Autodesk Fusion 360 part; units mm, degrees
(part 2 of 3)
  spline S18 degree 5 poles (-4.9086, 5.0572) (-4.9127, 5.0613) (-4.9209, 5.0695) (-4.9336, 5.0813) (-4.9513, 5.0962) (-4.9744, 5.1137) (-4.9983, 5.1304) (-5.0226, 5.1466) (-5.0473, 5.1625) (-5.0721, 5.1783) (-5.097, 5.1938) (-5.1223, 5.2091) (-5.1478, 5.224) (-5.1737, 5.2385) (-5.2, 5.2525) (-5.2266, 5.2662) (-5.2535, 5.2796) (-5.2806, 5.2926) (-5.3079, 5.3054) (-5.3354, 5.318) (-5.3631, 5.3303) (-5.391, 5.3423) (-5.4191, 5.3541) (-5.4474, 5.3656) (-5.476, 5.3768) (-5.5047, 5.3878) (-5.5336, 5.3984) (-5.5627, 5.4089) (-5.592, 5.4191) (-5.6215, 5.429) (-5.6511, 5.4387) (-5.6809, 5.4482) (-5.7108, 5.4574) (-5.7409, 5.4664) (-5.7712, 5.4751) (-5.8016, 5.4836) (-5.8322, 5.4919) (-5.8629, 5.4999) (-5.8938, 5.5077) (-5.9248, 5.5153) (-5.9559, 5.5226) (-5.9872, 5.5297) (-6.0186, 5.5366) (-6.0501, 5.5433) (-6.0818, 5.5497) (-6.1136, 5.5559) (-6.1456, 5.5619) (-6.1776, 5.5676) (-6.2098, 5.5731) (-6.2421, 5.5784) (-6.2745, 5.5835) (-6.307, 5.5884) (-6.3397, 5.593) (-6.3724, 5.5975) (-6.4053, 5.6017) (-6.4383, 5.6056) (-6.4713, 5.6094) (-6.5045, 5.613) (-6.5378, 5.6163) (-6.5712, 5.6194) (-6.6046, 5.6223) (-6.6382, 5.625) (-6.6719, 5.6274) (-6.7056, 5.6297) (-6.7395, 5.6317) (-6.7734, 5.6335) (-6.8075, 5.6351) (-6.8416, 5.6365) (-6.8758, 5.6377) (-6.9101, 5.6386) (-6.9444, 5.6394) (-6.972, 5.6398) (-6.9927, 5.64) (-7.0065, 5.6401) (-7.0134, 5.6402) knots 0 0 0 0 0 0 0.01428571 0.02857143 0.04285714 0.05714286 0.07142857 0.08571429 0.1 0.11428571 0.12857143 0.14285714 0.15714286 0.17142857 0.18571429 0.2 0.21428571 0.22857143 0.24285714 0.25714286 0.27142857 0.28571429 0.3 0.31428571 0.32857143 0.34285714 0.35714286 0.37142857 0.38571429 0.4 0.41428571 0.42857143 0.44285714 0.45714286 0.47142857 0.48571429 0.5 0.51428571 0.52857143 0.54285714 0.55714286 0.57142857 0.58571429 0.6 0.61428571 0.62857143 0.64285714 0.65714286 0.67142857 0.68571429 0.7 0.71428571 0.72857143 0.74285714 0.75714286 0.77142857 0.78571429 0.8 0.81428571 0.82857143 0.84285714 0.85714286 0.87142857 0.88571429 0.9 0.91428571 0.92857143 0.94285714 0.95714286 0.97142857 0.98571429 1 1 1 1 1 1
  arc A38 (-7.0134, 5.6402) -> (-7.5314, 4.9273) centre (0, 0) ccw
  spline S19 degree 5 poles (-7.5314, 4.9273) (-7.5292, 4.9207) (-7.5249, 4.9076) (-7.5182, 4.888) (-7.5093, 4.8619) (-7.498, 4.8294) (-7.4865, 4.7971) (-7.4748, 4.765) (-7.4629, 4.7329) (-7.4509, 4.7011) (-7.4387, 4.6693) (-7.4263, 4.6378) (-7.4137, 4.6064) (-7.401, 4.5751) (-7.3881, 4.544) (-7.375, 4.5131) (-7.3617, 4.4823) (-7.3482, 4.4516) (-7.3346, 4.4212) (-7.3208, 4.3909) (-7.3068, 4.3608) (-7.2927, 4.3308) (-7.2784, 4.301) (-7.2639, 4.2714) (-7.2492, 4.242) (-7.2343, 4.2127) (-7.2193, 4.1837) (-7.2041, 4.1548) (-7.1887, 4.1261) (-7.1732, 4.0976) (-7.1574, 4.0692) (-7.1415, 4.0411) (-7.1255, 4.0131) (-7.1092, 3.9854) (-7.0928, 3.9578) (-7.0762, 3.9305) (-7.0594, 3.9033) (-7.0425, 3.8764) (-7.0253, 3.8496) (-7.008, 3.8231) (-6.9905, 3.7968) (-6.9729, 3.7707) (-6.955, 3.7449) (-6.937, 3.7192) (-6.9188, 3.6938) (-6.9004, 3.6687) (-6.8819, 3.6437) (-6.8631, 3.619) (-6.8442, 3.5946) (-6.8251, 3.5704) (-6.8058, 3.5464) (-6.7863, 3.5227) (-6.7667, 3.4993) (-6.7468, 3.4763) (-6.7267, 3.4534) (-6.7064, 3.4309) (-6.686, 3.4086) (-6.6654, 3.3866) (-6.6446, 3.3649) (-6.6236, 3.3434) (-6.6024, 3.3224) (-6.5809, 3.3017) (-6.5591, 3.2816) (-6.537, 3.2619) (-6.5147, 3.2426) (-6.4922, 3.2236) (-6.4695, 3.2049) (-6.4468, 3.1864) (-6.4239, 3.1683) (-6.4006, 3.1507) (-6.3768, 3.1341) (-6.3572, 3.1219) (-6.342, 3.1135) (-6.3317, 3.1082) (-6.3265, 3.1056) knots -1 -1 -1 -1 -1 -1 -0.98571429 -0.97142857 -0.95714286 -0.94285714 -0.92857143 -0.91428571 -0.9 -0.88571429 -0.87142857 -0.85714286 -0.84285714 -0.82857143 -0.81428571 -0.8 -0.78571429 -0.77142857 -0.75714286 -0.74285714 -0.72857143 -0.71428571 -0.7 -0.68571429 -0.67142857 -0.65714286 -0.64285714 -0.62857143 -0.61428571 -0.6 -0.58571429 -0.57142857 -0.55714286 -0.54285714 -0.52857143 -0.51428571 -0.5 -0.48571429 -0.47142857 -0.45714286 -0.44285714 -0.42857143 -0.41428571 -0.4 -0.38571429 -0.37142857 -0.35714286 -0.34285714 -0.32857143 -0.31428571 -0.3 -0.28571429 -0.27142857 -0.25714286 -0.24285714 -0.22857143 -0.21428571 -0.2 -0.18571429 -0.17142857 -0.15714286 -0.14285714 -0.12857143 -0.11428571 -0.1 -0.08571429 -0.07142857 -0.05714286 -0.04285714 -0.02857143 -0.01428571 0 0 0 0 0 0
  line L19 (-6.3265, 3.1056) -> (-5.2636, 2.5839)
  arc A39 (-5.2172, 2.4516) -> (-5.2636, 2.5839) centre (-5.3077, 2.4941) ccw
  circle A40 centre (0, 0) radius 2.35
  dimension "d41" = 0.1
sketch "Diametrial Pitch Circle" plane through (0, 0, 0) normal (0, 0, 1) x (1, 0, 0)
  circle A0 centre (0, 0) radius 7.5 construction
sketch "Sketch6" plane through (0, 0, 0) normal (1, 0, 0) x (0, 1, 0)
  line L0 (0, 0) -> (0, 5)
  line L1 (0, 5) -> (10, 5)
  line L2 (10, 5) -> (10, 0)
  line L3 (10, 0) -> (0, 0)
  dimension "d13" = 5
  dimension "d14" = 10
  constraint coincident L0.start L3.end
  constraint vertical L0
  constraint perpendicular L0 L1
  constraint perpendicular L1 L2
  constraint perpendicular L0 L3
  measures "d13" distance of L0.start L0.end
  measures "d14" distance of L0.end L1.end
extrude "Extrude4" add sketch "Sketch6" along normal blind 38 separate body makes body 2
sketch "Sketch7" plane through (0, 10, 0) normal (0, 1, 0) x (-1, 0, 0)
  line L0 (0, 0) -> (0, 5)
  line L1 (0, 5) -> (-38, 5)
  line L2 (-38, 5) -> (-38, 0)
  line L3 (-38, 0) -> (0, 0)
  line L4 (-38, 5) -> (-30, 5)
  line L5 (-30, 5) -> (-30, 0)
  line L6 (-30, 0) -> (-38, 0)
  line L7 (-38, 0) -> (-38, 5)
  constraint horizontal L4
  constraint vertical L5
  constraint horizontal L6
  constraint vertical L7
  constraint coincident L3 L5.end
  constraint coincident L1.end L2.start
extrude "Extrude5" add sketch "Sketch7" along normal blind 110 contours L1 L2 L3 L4 L5 L6 L7 bodies 2
sketch "Sketch8" plane through (30, 0, 0) normal (-1, 0, 0) x (0, -1, 0)
  line L0 (-10, 0) -> (-10, 5)
  line L1 (-10, 5) -> (-120, 5)
  line L2 (-120, 5) -> (-120, 0)
  line L3 (-120, 0) -> (-10, 0)
  line L4 (-120, 5) -> (-110, 5)
  line L5 (-110, 5) -> (-110, 0)
  line L6 (-110, 0) -> (-120, 0)
  line L7 (-120, 0) -> (-120, 5)
  dimension "d19" = 10
  dimension "d20" = 5
  constraint horizontal L4
  constraint vertical L5
  constraint horizontal L6
  constraint vertical L7
  constraint coincident L1.end L2.start
  measures "d19" distance of L1.end L4.end
  measures "d20" distance of L1.end L2.end
extrude "Extrude6" add sketch "Sketch8" along normal blind 25 contours L1 L2 L3 L4 L5 L6 L7 bodies 2
sketch "Sketch9" plane through (0, 0, 5) normal (0, 0, 1) x (-1, 0, 0)
  line L0 (0, -10) -> (0, 0)
  line L1 (0, 0) -> (-38, 0)
  line L2 (-38, 0) -> (-38, -120)
  line L3 (-38, -120) -> (-5, -120)
  line L4 (-5, -120) -> (-5, -110)
  line L5 (-5, -110) -> (-30, -110)
  line L6 (-30, -110) -> (-30, -10)
  line L7 (-30, -10) -> (0, -10)
  line L8 (-38, -5) -> (-25, 0)
  line L9 (-38, -110) -> (-30, -120)
  line L10 (-30, -110) -> (-5, -120)
  line L11 (0, -4.5) -> (0, 0)
  line L12 (-4.5, 0) -> (0, 0)
  arc A0 (-4.5, 0) -> (0, -4.5) centre (0, 0) ccw
  circle A1 centre (0, 0) radius 2.35
  circle A2 centre (0, 0) radius 8.5
  dimension "d25" = 9
  dimension "d28" = 4.7
  dimension "d31" = 17
  constraint coincident L2 L8.start
  constraint coincident L1 L8.end
  constraint coincident L2 L9.start
  constraint coincident L3 L9.end
  constraint coincident L5.end L6.start
  constraint coincident L3.end L4.start
  constraint coincident L0.end L1.start
  constraint coincident L0 L11.start
  constraint coincident L1 L12.start
  constraint concentric A0 A2
  measures "d25" diameter of A0
  measures "d28" diameter of A1
  measures "d31" diameter of A2
extrude "Extrude7" cut sketch "Sketch9" against normal blind 20 contours L4 L5 L10 | L1 L2 L8 | L2 L3 L9 bodies 2
extrude "Extrude8" cut sketch "Sketch9" against normal blind 2 contours L0 L1 L11 L12 A0 A1 | L0 L1 L11 L12 A1 picked at (-1.5587, -0.1115) bodies 2
extrude "Extrude9" cut sketch "Sketch9" against normal blind 20 contours L0 L1 L11 L12 A1 picked at (-1.5587, -0.1115) bodies 2
split "Split3" by plane through (0, 0, 2) normal (0, 0, 1) bodies 1 2 makes body 3 at (21.6667, 116.6667, 5)
combine "Combine1" operation add target body 3 tool bodies 2
copy_body "CopyPasteBodies2" bodies 1 makes body 4
move_body "Move3" bodies 4 to x (1, 0, 0) y (0, 1, 0) z (0, 0, 1) at (-15, 0, 0)
move_body "Move4" bodies 1 to x (0.951057, 0.309017, 0) y (-0.309017, 0.951057, 0) z (0, 0, 1) at (0, 0, 0)
mirror "Mirror2" about plane through (0, 0, 0) normal (1, 0, 0) of bodies 3 makes body 5
move_body "Move5" bodies 5 to x (1, 0, 0) y (0, 1, 0) z (0, 0, 1) at (-15, 0, 0)
move_body "Move6" bodies 3 1 to x (1, 0, 0) y (0, 1, 0) z (0, 0, 1) at (15, 0, 0)
sketch "Sketch15" plane through (0, 0, 2) normal (0, 0, 1) x (-1, 0, 0)
  arc A0 (9.7828, 2.4516) -> (9.3382, 1.0832) centre (15, 0) ccw
  arc A1 (9.2229, 1.0035) -> (9.3382, 1.0832) centre (9.24, 1.102) ccw
  line L0 (9.2229, 1.0035) -> (8.0563, 1.2061)
  spline S0 degree 5 poles (8.0563, 1.2061) (8.0506, 1.2071) (8.0391, 1.2089) (8.0219, 1.211) (7.9989, 1.2127) (7.9699, 1.2132) (7.9407, 1.2127) (7.9115, 1.2115) (7.8822, 1.2099) (7.8529, 1.208) (7.8236, 1.2059) (7.7942, 1.2034) (7.7647, 1.2005) (7.7353, 1.197) (7.7057, 1.1929) (7.6762, 1.1884) (7.6466, 1.1833) (7.617, 1.178) (7.5874, 1.1723) (7.5578, 1.1663) (7.5281, 1.1599) (7.4985, 1.1533) (7.4688, 1.1463) (7.4391, 1.139) (7.4094, 1.1313) (7.3798, 1.1232) (7.3501, 1.1148) (7.3204, 1.1062) (7.2907, 1.0972) (7.2611, 1.0879) (7.2314, 1.0784) (7.2017, 1.0685) (7.1721, 1.0584) (7.1425, 1.048) (7.1128, 1.0372) (7.0832, 1.0262) (7.0536, 1.015) (7.0241, 1.0034) (6.9945, 0.9916) (6.965, 0.9795) (6.9355, 0.9671) (6.906, 0.9545) (6.8765, 0.9416) (6.8471, 0.9284) (6.8177, 0.915) (6.7883, 0.9013) (6.759, 0.8874) (6.7296, 0.8732) (6.7004, 0.8587) (6.6711, 0.844) (6.6419, 0.8291) (6.6127, 0.8139) (6.5836, 0.7985) (6.5545, 0.7828) (6.5254, 0.7669) (6.4964, 0.7508) (6.4675, 0.7344) (6.4385, 0.7177) (6.4097, 0.7009) (6.3808, 0.6838) (6.352, 0.6664) (6.3233, 0.6489) (6.2946, 0.6311) (6.266, 0.613) (6.2374, 0.5948) (6.2089, 0.5763) (6.1804, 0.5576) (6.152, 0.5387) (6.1236, 0.5195) (6.0953, 0.5001) (6.0671, 0.4805) (6.0445, 0.4647) (6.0277, 0.4527) (6.0164, 0.4446) (6.0108, 0.4406) knots 0 0 0 0 0 0 0.01428571 0.02857143 0.04285714 0.05714286 0.07142857 0.08571429 0.1 0.11428571 0.12857143 0.14285714 0.15714286 0.17142857 0.18571429 0.2 0.21428571 0.22857143 0.24285714 0.25714286 0.27142857 0.28571429 0.3 0.31428571 0.32857143 0.34285714 0.35714286 0.37142857 0.38571429 0.4 0.41428571 0.42857143 0.44285714 0.45714286 0.47142857 0.48571429 0.5 0.51428571 0.52857143 0.54285714 0.55714286 0.57142857 0.58571429 0.6 0.61428571 0.62857143 0.64285714 0.65714286 0.67142857 0.68571429 0.7 0.71428571 0.72857143 0.74285714 0.75714286 0.77142857 0.78571429 0.8 0.81428571 0.82857143 0.84285714 0.85714286 0.87142857 0.88571429 0.9 0.91428571 0.92857143 0.94285714 0.95714286 0.97142857 0.98571429 1 1 1 1 1 1
  arc A2 (6.0108, 0.4406) -> (6.0108, -0.4406) centre (15, 0) ccw
  spline S1 degree 5 poles (6.0108, -0.4406) (6.0164, -0.4446) (6.0277, -0.4527) (6.0445, -0.4647) (6.0671, -0.4805) (6.0953, -0.5001) (6.1236, -0.5195) (6.152, -0.5387) (6.1804, -0.5576) (6.2089, -0.5763) (6.2374, -0.5948) (6.266, -0.613) (6.2946, -0.6311) (6.3233, -0.6489) (6.352, -0.6664) (6.3808, -0.6838) (6.4097, -0.7009) (6.4385, -0.7177) (6.4675, -0.7344) (6.4964, -0.7508) (6.5254, -0.7669) (6.5545, -0.7828) (6.5836, -0.7985) (6.6127, -0.8139) (6.6419, -0.8291) (6.6711, -0.844) (6.7004, -0.8587) (6.7296, -0.8732) (6.759, -0.8874) (6.7883, -0.9013) (6.8177, -0.915) (6.8471, -0.9284) (6.8765, -0.9416) (6.906, -0.9545) (6.9355, -0.9671) (6.965, -0.9795) (6.9945, -0.9916) (7.0241, -1.0034) (7.0536, -1.015) (7.0832, -1.0262) (7.1128, -1.0372) (7.1425, -1.048) (7.1721, -1.0584) (7.2017, -1.0685) (7.2314, -1.0784) (7.2611, -1.0879) (7.2907, -1.0972) (7.3204, -1.1062) (7.3501, -1.1148) (7.3798, -1.1232) (7.4094, -1.1313) (7.4391, -1.139) (7.4688, -1.1463) (7.4985, -1.1533) (7.5281, -1.1599) (7.5578, -1.1663) (7.5874, -1.1723) (7.617, -1.178) (7.6466, -1.1833) (7.6762, -1.1884) (7.7057, -1.1929) (7.7353, -1.197) (7.7647, -1.2005) (7.7942, -1.2034) (7.8236, -1.2059) (7.8529, -1.208) (7.8822, -1.2099) (7.9115, -1.2115) (7.9407, -1.2127) (7.9699, -1.2132) (7.9989, -1.2127) (8.0219, -1.211) (8.0391, -1.2089) (8.0506, -1.2071) (8.0563, -1.2061) knots -1 -1 -1 -1 -1 -1 -0.98571429 -0.97142857 -0.95714286 -0.94285714 -0.92857143 -0.91428571 -0.9 -0.88571429 -0.87142857 -0.85714286 -0.84285714 -0.82857143 -0.81428571 -0.8 -0.78571429 -0.77142857 -0.75714286 -0.74285714 -0.72857143 -0.71428571 -0.7 -0.68571429 -0.67142857 -0.65714286 -0.64285714 -0.62857143 -0.61428571 -0.6 -0.58571429 -0.57142857 -0.55714286 -0.54285714 -0.52857143 -0.51428571 -0.5 -0.48571429 -0.47142857 -0.45714286 -0.44285714 -0.42857143 -0.41428571 -0.4 -0.38571429 -0.37142857 -0.35714286 -0.34285714 -0.32857143 -0.31428571 -0.3 -0.28571429 -0.27142857 -0.25714286 -0.24285714 -0.22857143 -0.21428571 -0.2 -0.18571429 -0.17142857 -0.15714286 -0.14285714 -0.12857143 -0.11428571 -0.1 -0.08571429 -0.07142857 -0.05714286 -0.04285714 -0.02857143 -0.01428571 0 0 0 0 0 0
  line L1 (8.0563, -1.2061) -> (9.2229, -1.0035)
  arc A3 (9.3382, -1.0832) -> (9.2229, -1.0035) centre (9.24, -1.102) ccw
  arc A4 (9.3382, -1.0832) -> (9.7828, -2.4516) centre (15, 0) ccw
  arc A5 (9.7364, -2.5839) -> (9.7828, -2.4516) centre (9.6923, -2.4941) ccw
  line L2 (9.7364, -2.5839) -> (8.6735, -3.1056)
  spline S2 degree 5 poles (8.6735, -3.1056) (8.6683, -3.1082) (8.658, -3.1135) (8.6428, -3.1219) (8.6232, -3.1341) (8.5994, -3.1507) (8.5761, -3.1683) (8.5532, -3.1864) (8.5305, -3.2049) (8.5078, -3.2236) (8.4853, -3.2426) (8.463, -3.2619) (8.4409, -3.2816) (8.4191, -3.3017) (8.3976, -3.3224) (8.3764, -3.3434) (8.3554, -3.3649) (8.3346, -3.3866) (8.314, -3.4086) (8.2936, -3.4309) (8.2733, -3.4534) (8.2532, -3.4763) (8.2333, -3.4993) (8.2137, -3.5227) (8.1942, -3.5464) (8.1749, -3.5704) (8.1558, -3.5946) (8.1369, -3.619) (8.1181, -3.6437) (8.0996, -3.6687) (8.0812, -3.6938) (8.063, -3.7192) (8.045, -3.7449) (8.0271, -3.7707) (8.0095, -3.7968) (7.992, -3.8231) (7.9747, -3.8496) (7.9575, -3.8764) (7.9406, -3.9033) (7.9238, -3.9305) (7.9072, -3.9578) (7.8908, -3.9854) (7.8745, -4.0131) (7.8585, -4.0411) (7.8426, -4.0692) (7.8268, -4.0976) (7.8113, -4.1261) (7.7959, -4.1548) (7.7807, -4.1837) (7.7657, -4.2127) (7.7508, -4.242) (7.7361, -4.2714) (7.7216, -4.301) (7.7073, -4.3308) (7.6932, -4.3608) (7.6792, -4.3909) (7.6654, -4.4212) (7.6518, -4.4516) (7.6383, -4.4823) (7.625, -4.5131) (7.6119, -4.544) (7.599, -4.5751) (7.5863, -4.6064) (7.5737, -4.6378) (7.5613, -4.6693) (7.5491, -4.7011) (7.5371, -4.7329) (7.5252, -4.765) (7.5135, -4.7971) (7.502, -4.8294) (7.4907, -4.8619) (7.4818, -4.888) (7.4751, -4.9076) (7.4708, -4.9207) (7.4686, -4.9273) knots 0 0 0 0 0 0 0.01428571 0.02857143 0.04285714 0.05714286 0.07142857 0.08571429 0.1 0.11428571 0.12857143 0.14285714 0.15714286 0.17142857 0.18571429 0.2 0.21428571 0.22857143 0.24285714 0.25714286 0.27142857 0.28571429 0.3 0.31428571 0.32857143 0.34285714 0.35714286 0.37142857 0.38571429 0.4 0.41428571 0.42857143 0.44285714 0.45714286 0.47142857 0.48571429 0.5 0.51428571 0.52857143 0.54285714 0.55714286 0.57142857 0.58571429 0.6 0.61428571 0.62857143 0.64285714 0.65714286 0.67142857 0.68571429 0.7 0.71428571 0.72857143 0.74285714 0.75714286 0.77142857 0.78571429 0.8 0.81428571 0.82857143 0.84285714 0.85714286 0.87142857 0.88571429 0.9 0.91428571 0.92857143 0.94285714 0.95714286 0.97142857 0.98571429 1 1 1 1 1 1
  arc A6 (7.4686, -4.9273) -> (7.9866, -5.6402) centre (15, 0) ccw
  spline S3 degree 5 poles (7.9866, -5.6402) (7.9935, -5.6401) (8.0073, -5.64) (8.028, -5.6398) (8.0556, -5.6394) (8.0899, -5.6386) (8.1242, -5.6377) (8.1584, -5.6365) (8.1925, -5.6351) (8.2266, -5.6335) (8.2605, -5.6317) (8.2944, -5.6297) (8.3281, -5.6274) (8.3618, -5.625) (8.3954, -5.6223) (8.4288, -5.6194) (8.4622, -5.6163) (8.4955, -5.613) (8.5287, -5.6094) (8.5617, -5.6056) (8.5947, -5.6017) (8.6276, -5.5975) (8.6603, -5.593) (8.693, -5.5884) (8.7255, -5.5835) (8.7579, -5.5784) (8.7902, -5.5731) (8.8224, -5.5676) (8.8544, -5.5619) (8.8864, -5.5559) (8.9182, -5.5497) (8.9499, -5.5433) (8.9814, -5.5366) (9.0128, -5.5297) (9.0441, -5.5226) (9.0752, -5.5153) (9.1062, -5.5077) (9.1371, -5.4999) (9.1678, -5.4919) (9.1984, -5.4836) (9.2288, -5.4751) (9.2591, -5.4664) (9.2892, -5.4574) (9.3191, -5.4482) (9.3489, -5.4387) (9.3785, -5.429) (9.408, -5.4191) (9.4373, -5.4089) (9.4664, -5.3984) (9.4953, -5.3878) (9.524, -5.3768) (9.5526, -5.3656) (9.5809, -5.3541) (9.609, -5.3423) (9.6369, -5.3303) (9.6646, -5.318) (9.6921, -5.3054) (9.7194, -5.2926) (9.7465, -5.2796) (9.7734, -5.2662) (9.8, -5.2525) (9.8263, -5.2385) (9.8522, -5.224) (9.8777, -5.2091) (9.903, -5.1938) (9.9279, -5.1783) (9.9527, -5.1625) (9.9774, -5.1466) (10.0017, -5.1304) (10.0256, -5.1137) (10.0487, -5.0962) (10.0664, -5.0813) (10.0791, -5.0695) (10.0873, -5.0613) (10.0914, -5.0572) knots -1 -1 -1 -1 -1 -1 -0.98571429 -0.97142857 -0.95714286 -0.94285714 -0.92857143 -0.91428571 -0.9 -0.88571429 -0.87142857 -0.85714286 -0.84285714 -0.82857143 -0.81428571 -0.8 -0.78571429 -0.77142857 -0.75714286 -0.74285714 -0.72857143 -0.71428571 -0.7 -0.68571429 -0.67142857 -0.65714286 -0.64285714 -0.62857143 -0.61428571 -0.6 -0.58571429 -0.57142857 -0.55714286 -0.54285714 -0.52857143 -0.51428571 -0.5 -0.48571429 -0.47142857 -0.45714286 -0.44285714 -0.42857143 -0.41428571 -0.4 -0.38571429 -0.37142857 -0.35714286 -0.34285714 -0.32857143 -0.31428571 -0.3 -0.28571429 -0.27142857 -0.25714286 -0.24285714 -0.22857143 -0.21428571 -0.2 -0.18571429 -0.17142857 -0.15714286 -0.14285714 -0.12857143 -0.11428571 -0.1 -0.08571429 -0.07142857 -0.05714286 -0.04285714 -0.02857143 -0.01428571 0 0 0 0 0 0
  line L3 (10.0914, -5.0572) -> (10.916, -4.2076)
  arc A7 (11.0562, -4.2043) -> (10.916, -4.2076) centre (10.9878, -4.2772) ccw
  arc A8 (11.0562, -4.2043) -> (12.2202, -5.05) centre (15, 0) ccw
  arc A9 (12.2604, -5.1843) -> (12.2202, -5.05) centre (12.172, -5.1376) ccw
  line L4 (12.2604, -5.1843) -> (11.7072, -6.2312)
  spline S4 degree 5 poles (11.7072, -6.2312) (11.7045, -6.2363) (11.6992, -6.2466) (11.6919, -6.2623) (11.6832, -6.2838) (11.6737, -6.3112) (11.6652, -6.339) (11.6574, -6.3672) (11.6498, -6.3955) (11.6425, -6.424) (11.6355, -6.4526) (11.6287, -6.4813) (11.6225, -6.5102) (11.6167, -6.5393) (11.6114, -6.5686) (11.6066, -6.5981) (11.6022, -6.6278) (11.5982, -6.6576) (11.5945, -6.6876) (11.591, -6.7176) (11.5879, -6.7477) (11.585, -6.778) (11.5825, -6.8084) (11.5804, -6.8389) (11.5785, -6.8695) (11.577, -6.9002) (11.5758, -6.931) (11.5748, -6.9619) (11.5742, -6.9929) (11.5738, -7.024) (11.5738, -7.0551) (11.574, -7.0864) (11.5744, -7.1177) (11.5752, -7.1491) (11.5762, -7.1806) (11.5776, -7.2122) (11.5792, -7.2438) (11.581, -7.2755) (11.5831, -7.3073) (11.5855, -7.3391) (11.5882, -7.371) (11.5911, -7.4029) (11.5942, -7.4349) (11.5977, -7.467) (11.6013, -7.4991) (11.6053, -7.5313) (11.6094, -7.5635) (11.6139, -7.5958) (11.6186, -7.6281) (11.6235, -7.6604) (11.6287, -7.6928) (11.6341, -7.7253) (11.6398, -7.7577) (11.6457, -7.7902) (11.6518, -7.8228) (11.6582, -7.8554) (11.6649, -7.888) (11.6718, -7.9206) (11.6789, -7.9533) (11.6862, -7.986) (11.6938, -8.0188) (11.7017, -8.0515) (11.7097, -8.0843) (11.718, -8.1171) (11.7265, -8.1499) (11.7353, -8.1828) (11.7443, -8.2156) (11.7535, -8.2485) (11.763, -8.2814) (11.7727, -8.3143) (11.7826, -8.3472) (11.7907, -8.3736) (11.7969, -8.3933) (11.801, -8.4065) (11.8031, -8.4131) knots 0 0 0 0 0 0 0.01428571 0.02857143 0.04285714 0.05714286 0.07142857 0.08571429 0.1 0.11428571 0.12857143 0.14285714 0.15714286 0.17142857 0.18571429 0.2 0.21428571 0.22857143 0.24285714 0.25714286 0.27142857 0.28571429 0.3 0.31428571 0.32857143 0.34285714 0.35714286 0.37142857 0.38571429 0.4 0.41428571 0.42857143 0.44285714 0.45714286 0.47142857 0.48571429 0.5 0.51428571 0.52857143 0.54285714 0.55714286 0.57142857 0.58571429 0.6 0.61428571 0.62857143 0.64285714 0.65714286 0.67142857 0.68571429 0.7 0.71428571 0.72857143 0.74285714 0.75714286 0.77142857 0.78571429 0.8 0.81428571 0.82857143 0.84285714 0.85714286 0.87142857 0.88571429 0.9 0.91428571 0.92857143 0.94285714 0.95714286 0.97142857 0.98571429 1 1 1 1 1 1
  arc A10 (11.8031, -8.4131) -> (12.6412, -8.6854) centre (15, 0) ccw
  spline S5 degree 5 poles (12.6412, -8.6854) (12.6468, -8.6813) (12.6579, -8.6731) (12.6745, -8.6607) (12.6966, -8.6442) (12.724, -8.6234) (12.7511, -8.6025) (12.7781, -8.5814) (12.8049, -8.5602) (12.8315, -8.5389) (12.8579, -8.5175) (12.8841, -8.496) (12.9101, -8.4743) (12.9359, -8.4525) (12.9614, -8.4306) (12.9868, -8.4086) (13.012, -8.3865) (13.037, -8.3642) (13.0617, -8.3419) (13.0863, -8.3194) (13.1106, -8.2968) (13.1347, -8.2741) (13.1586, -8.2512) (13.1823, -8.2283) (13.2057, -8.2052) (13.229, -8.1821) (13.252, -8.1588) (13.2748, -8.1354) (13.2973, -8.1119) (13.3196, -8.0883) (13.3417, -8.0646) (13.3636, -8.0408) (13.3852, -8.0168) (13.4066, -7.9928) (13.4277, -7.9687) (13.4486, -7.9444) (13.4692, -7.9201) (13.4896, -7.8956) (13.5097, -7.8711) (13.5296, -7.8464) (13.5492, -7.8217) (13.5686, -7.7968) (13.5876, -7.7719) (13.6064, -7.7468) (13.625, -7.7216) (13.6432, -7.6964) (13.6612, -7.671) (13.6789, -7.6456) (13.6963, -7.62) (13.7135, -7.5944) (13.7303, -7.5686) (13.7468, -7.5428) (13.7629, -7.5168) (13.7788, -7.4908) (13.7942, -7.4646) (13.8094, -7.4384) (13.8243, -7.4121) (13.8389, -7.3857) (13.8531, -7.3592) (13.867, -7.3326) (13.8805, -7.3059) (13.8935, -7.2791) (13.9059, -7.2521) (13.9178, -7.225) (13.9292, -7.1978) (13.9403, -7.1706) (13.9511, -7.1433) (13.9617, -7.1159) (13.9719, -7.0885) (13.9814, -7.061) (13.9898, -7.0332) (13.9954, -7.0108) (13.9987, -6.9937) (14.0005, -6.9823) (14.0014, -6.9766) knots -1 -1 -1 -1 -1 -1 -0.98571429 -0.97142857 -0.95714286 -0.94285714 -0.92857143 -0.91428571 -0.9 -0.88571429 -0.87142857 -0.85714286 -0.84285714 -0.82857143 -0.81428571 -0.8 -0.78571429 -0.77142857 -0.75714286 -0.74285714 -0.72857143 -0.71428571 -0.7 -0.68571429 -0.67142857 -0.65714286 -0.64285714 -0.62857143 -0.61428571 -0.6 -0.58571429 -0.57142857 -0.55714286 -0.54285714 -0.52857143 -0.51428571 -0.5 -0.48571429 -0.47142857 -0.45714286 -0.44285714 -0.42857143 -0.41428571 -0.4 -0.38571429 -0.37142857 -0.35714286 -0.34285714 -0.32857143 -0.31428571 -0.3 -0.28571429 -0.27142857 -0.25714286 -0.24285714 -0.22857143 -0.21428571 -0.2 -0.18571429 -0.17142857 -0.15714286 -0.14285714 -0.12857143 -0.11428571 -0.1 -0.08571429 -0.07142857 -0.05714286 -0.04285714 -0.02857143 -0.01428571 0 0 0 0 0 0
  line L5 (14.0014, -6.9766) -> (14.1691, -5.8045)
  arc A11 (14.2806, -5.7194) -> (14.1691, -5.8045) centre (14.2681, -5.8187) ccw
  arc A12 (14.2806, -5.7194) -> (15.7194, -5.7194) centre (15, 0) ccw
  arc A13 (15.8309, -5.8045) -> (15.7194, -5.7194) centre (15.7319, -5.8187) ccw
  line L6 (15.8309, -5.8045) -> (15.9986, -6.9766)
  spline S6 degree 5 poles (15.9986, -6.9766) (15.9995, -6.9823) (16.0013, -6.9937) (16.0046, -7.0108) (16.0102, -7.0332) (16.0186, -7.061) (16.0281, -7.0885) (16.0383, -7.1159) (16.0489, -7.1433) (16.0597, -7.1706) (16.0708, -7.1978) (16.0822, -7.225) (16.0941, -7.2521) (16.1065, -7.2791) (16.1195, -7.3059) (16.133, -7.3326) (16.1469, -7.3592) (16.1611, -7.3857) (16.1757, -7.4121) (16.1906, -7.4384) (16.2058, -7.4646) (16.2212, -7.4908) (16.2371, -7.5168) (16.2532, -7.5428) (16.2697, -7.5686) (16.2865, -7.5944) (16.3037, -7.62) (16.3211, -7.6456) (16.3388, -7.671) (16.3568, -7.6964) (16.375, -7.7216) (16.3936, -7.7468) (16.4124, -7.7719) (16.4314, -7.7968) (16.4508, -7.8217) (16.4704, -7.8464) (16.4903, -7.8711) (16.5104, -7.8956) (16.5308, -7.9201) (16.5514, -7.9444) (16.5723, -7.9687) (16.5934, -7.9928) (16.6148, -8.0168) (16.6364, -8.0408) (16.6583, -8.0646) (16.6804, -8.0883) (16.7027, -8.1119) (16.7252, -8.1354) (16.748, -8.1588) (16.771, -8.1821) (16.7943, -8.2052) (16.8177, -8.2283) (16.8414, -8.2512) (16.8653, -8.2741) (16.8894, -8.2968) (16.9137, -8.3194) (16.9383, -8.3419) (16.963, -8.3642) (16.988, -8.3865) (17.0132, -8.4086) (17.0386, -8.4306) (17.0641, -8.4525) (17.0899, -8.4743) (17.1159, -8.496) (17.1421, -8.5175) (17.1685, -8.5389) (17.1951, -8.5602) (17.2219, -8.5814) (17.2489, -8.6025) (17.276, -8.6234) (17.3034, -8.6442) (17.3255, -8.6607) (17.3421, -8.6731) (17.3532, -8.6813) (17.3588, -8.6854) knots 0 0 0 0 0 0 0.01428571 0.02857143 0.04285714 0.05714286 0.07142857 0.08571429 0.1 0.11428571 0.12857143 0.14285714 0.15714286 0.17142857 0.18571429 0.2 0.21428571 0.22857143 0.24285714 0.25714286 0.27142857 0.28571429 0.3 0.31428571 0.32857143 0.34285714 0.35714286 0.37142857 0.38571429 0.4 0.41428571 0.42857143 0.44285714 0.45714286 0.47142857 0.48571429 0.5 0.51428571 0.52857143 0.54285714 0.55714286 0.57142857 0.58571429 0.6 0.61428571 0.62857143 0.64285714 0.65714286 0.67142857 0.68571429 0.7 0.71428571 0.72857143 0.74285714 0.75714286 0.77142857 0.78571429 0.8 0.81428571 0.82857143 0.84285714 0.85714286 0.87142857 0.88571429 0.9 0.91428571 0.92857143 0.94285714 0.95714286 0.97142857 0.98571429 1 1 1 1 1 1
  arc A14 (17.3588, -8.6854) -> (18.1969, -8.4131) centre (15, 0) ccw
  spline S7 degree 5 poles (18.1969, -8.4131) (18.199, -8.4065) (18.2031, -8.3933) (18.2093, -8.3736) (18.2174, -8.3472) (18.2273, -8.3143) (18.237, -8.2814) (18.2465, -8.2485) (18.2557, -8.2156) (18.2647, -8.1828) (18.2735, -8.1499) (18.282, -8.1171) (18.2903, -8.0843) (18.2983, -8.0515) (18.3062, -8.0188) (18.3138, -7.986) (18.3211, -7.9533) (18.3282, -7.9206) (18.3351, -7.888) (18.3418, -7.8554) (18.3482, -7.8228) (18.3543, -7.7902) (18.3602, -7.7577) (18.3659, -7.7253) (18.3713, -7.6928) (18.3765, -7.6604) (18.3814, -7.6281) (18.3861, -7.5958) (18.3906, -7.5635) (18.3947, -7.5313) (18.3987, -7.4991) (18.4023, -7.467) (18.4058, -7.4349) (18.4089, -7.4029) (18.4118, -7.371) (18.4145, -7.3391) (18.4169, -7.3073) (18.419, -7.2755) (18.4208, -7.2438) (18.4224, -7.2122) (18.4238, -7.1806) (18.4248, -7.1491) (18.4256, -7.1177) (18.426, -7.0864) (18.4262, -7.0551) (18.4262, -7.024) (18.4258, -6.9929) (18.4252, -6.9619) (18.4242, -6.931) (18.423, -6.9002) (18.4215, -6.8695) (18.4196, -6.8389) (18.4175, -6.8084) (18.415, -6.778) (18.4121, -6.7477) (18.409, -6.7176) (18.4055, -6.6876) (18.4018, -6.6576) (18.3978, -6.6278) (18.3934, -6.5981) (18.3886, -6.5686) (18.3833, -6.5393) (18.3775, -6.5102) (18.3713, -6.4813) (18.3645, -6.4526) (18.3575, -6.424) (18.3502, -6.3955) (18.3426, -6.3672) (18.3348, -6.339) (18.3263, -6.3112) (18.3168, -6.2838) (18.3081, -6.2623) (18.3008, -6.2466) (18.2955, -6.2363) (18.2928, -6.2312) knots -1 -1 -1 -1 -1 -1 -0.98571429 -0.97142857 -0.95714286 -0.94285714 -0.92857143 -0.91428571 -0.9 -0.88571429 -0.87142857 -0.85714286 -0.84285714 -0.82857143 -0.81428571 -0.8 -0.78571429 -0.77142857 -0.75714286 -0.74285714 -0.72857143 -0.71428571 -0.7 -0.68571429 -0.67142857 -0.65714286 -0.64285714 -0.62857143 -0.61428571 -0.6 -0.58571429 -0.57142857 -0.55714286 -0.54285714 -0.52857143 -0.51428571 -0.5 -0.48571429 -0.47142857 -0.45714286 -0.44285714 -0.42857143 -0.41428571 -0.4 -0.38571429 -0.37142857 -0.35714286 -0.34285714 -0.32857143 -0.31428571 -0.3 -0.28571429 -0.27142857 -0.25714286 -0.24285714 -0.22857143 -0.21428571 -0.2 -0.18571429 -0.17142857 -0.15714286 -0.14285714 -0.12857143 -0.11428571 -0.1 -0.08571429 -0.07142857 -0.05714286 -0.04285714 -0.02857143 -0.01428571 0 0 0 0 0 0
  line L7 (18.2928, -6.2312) -> (17.7396, -5.1843)
  arc A15 (17.7798, -5.05) -> (17.7396, -5.1843) centre (17.828, -5.1376) ccw
  arc A16 (17.7798, -5.05) -> (18.9438, -4.2043) centre (15, 0) ccw
  arc A17 (19.084, -4.2076) -> (18.9438, -4.2043) centre (19.0122, -4.2772) ccw
  line L8 (19.084, -4.2076) -> (19.9086, -5.0572)
  spline S8 degree 5 poles (19.9086, -5.0572) (19.9127, -5.0613) (19.9209, -5.0695) (19.9336, -5.0813) (19.9513, -5.0962) (19.9744, -5.1137) (19.9983, -5.1304) (20.0226, -5.1466) (20.0473, -5.1625) (20.0721, -5.1783) (20.097, -5.1938) (20.1223, -5.2091) (20.1478, -5.224) (20.1737, -5.2385) (20.2, -5.2525) (20.2266, -5.2662) (20.2535, -5.2796) (20.2806, -5.2926) (20.3079, -5.3054) (20.3354, -5.318) (20.3631, -5.3303) (20.391, -5.3423) (20.4191, -5.3541) (20.4474, -5.3656) (20.476, -5.3768) (20.5047, -5.3878) (20.5336, -5.3984) (20.5627, -5.4089) (20.592, -5.4191) (20.6215, -5.429) (20.6511, -5.4387) (20.6809, -5.4482) (20.7108, -5.4574) (20.7409, -5.4664) (20.7712, -5.4751) (20.8016, -5.4836) (20.8322, -5.4919) (20.8629, -5.4999) (20.8938, -5.5077) (20.9248, -5.5153) (20.9559, -5.5226) (20.9872, -5.5297) (21.0186, -5.5366) (21.0501, -5.5433) (21.0818, -5.5497) (21.1136, -5.5559) (21.1456, -5.5619) (21.1776, -5.5676) (21.2098, -5.5731) (21.2421, -5.5784) (21.2745, -5.5835) (21.307, -5.5884) (21.3397, -5.593) (21.3724, -5.5975) (21.4053, -5.6017) (21.4383, -5.6056) (21.4713, -5.6094) (21.5045, -5.613) (21.5378, -5.6163) (21.5712, -5.6194) (21.6046, -5.6223) (21.6382, -5.625) (21.6719, -5.6274) (21.7056, -5.6297) (21.7395, -5.6317) (21.7734, -5.6335) (21.8075, -5.6351) (21.8416, -5.6365) (21.8758, -5.6377) (21.9101, -5.6386) (21.9444, -5.6394) (21.972, -5.6398) (21.9927, -5.64) (22.0065, -5.6401) (22.0134, -5.6402) knots 0 0 0 0 0 0 0.01428571 0.02857143 0.04285714 0.05714286 0.07142857 0.08571429 0.1 0.11428571 0.12857143 0.14285714 0.15714286 0.17142857 0.18571429 0.2 0.21428571 0.22857143 0.24285714 0.25714286 0.27142857 0.28571429 0.3 0.31428571 0.32857143 0.34285714 0.35714286 0.37142857 0.38571429 0.4 0.41428571 0.42857143 0.44285714 0.45714286 0.47142857 0.48571429 0.5 0.51428571 0.52857143 0.54285714 0.55714286 0.57142857 0.58571429 0.6 0.61428571 0.62857143 0.64285714 0.65714286 0.67142857 0.68571429 0.7 0.71428571 0.72857143 0.74285714 0.75714286 0.77142857 0.78571429 0.8 0.81428571 0.82857143 0.84285714 0.85714286 0.87142857 0.88571429 0.9 0.91428571 0.92857143 0.94285714 0.95714286 0.97142857 0.98571429 1 1 1 1 1 1
  arc A18 (22.0134, -5.6402) -> (22.5314, -4.9273) centre (15, 0) ccw
  spline S9 degree 5 poles (22.5314, -4.9273) (22.5292, -4.9207) (22.5249, -4.9076) (22.5182, -4.888) (22.5093, -4.8619) (22.498, -4.8294) (22.4865, -4.7971) (22.4748, -4.765) (22.4629, -4.7329) (22.4509, -4.7011) (22.4387, -4.6693) (22.4263, -4.6378) (22.4137, -4.6064) (22.401, -4.5751) (22.3881, -4.544) (22.375, -4.5131) (22.3617, -4.4823) (22.3482, -4.4516) (22.3346, -4.4212) (22.3208, -4.3909) (22.3068, -4.3608) (22.2927, -4.3308) (22.2784, -4.301) (22.2639, -4.2714) (22.2492, -4.242) (22.2343, -4.2127) (22.2193, -4.1837) (22.2041, -4.1548) (22.1887, -4.1261) (22.1732, -4.0976) (22.1574, -4.0692) (22.1415, -4.0411) (22.1255, -4.0131) (22.1092, -3.9854) (22.0928, -3.9578) (22.0762, -3.9305) (22.0594, -3.9033) (22.0425, -3.8764) (22.0253, -3.8496) (22.008, -3.8231) (21.9905, -3.7968) (21.9729, -3.7707) (21.955, -3.7449) (21.937, -3.7192) (21.9188, -3.6938) (21.9004, -3.6687) (21.8819, -3.6437) (21.8631, -3.619) (21.8442, -3.5946) (21.8251, -3.5704) (21.8058, -3.5464) (21.7863, -3.5227) (21.7667, -3.4993) (21.7468, -3.4763) (21.7267, -3.4534) (21.7064, -3.4309) (21.686, -3.4086) (21.6654, -3.3866) (21.6446, -3.3649) (21.6236, -3.3434) (21.6024, -3.3224) (21.5809, -3.3017) (21.5591, -3.2816) (21.537, -3.2619) (21.5147, -3.2426) (21.4922, -3.2236) (21.4695, -3.2049) (21.4468, -3.1864) (21.4239, -3.1683) (21.4006, -3.1507) (21.3768, -3.1341) (21.3572, -3.1219) (21.342, -3.1135) (21.3317, -3.1082) (21.3265, -3.1056) knots -1 -1 -1 -1 -1 -1 -0.98571429 -0.97142857 -0.95714286 -0.94285714 -0.92857143 -0.91428571 -0.9 -0.88571429 -0.87142857 -0.85714286 -0.84285714 -0.82857143 -0.81428571 -0.8 -0.78571429 -0.77142857 -0.75714286 -0.74285714 -0.72857143 -0.71428571 -0.7 -0.68571429 -0.67142857 -0.65714286 -0.64285714 -0.62857143 -0.61428571 -0.6 -0.58571429 -0.57142857 -0.55714286 -0.54285714 -0.52857143 -0.51428571 -0.5 -0.48571429 -0.47142857 -0.45714286 -0.44285714 -0.42857143 -0.41428571 -0.4 -0.38571429 -0.37142857 -0.35714286 -0.34285714 -0.32857143 -0.31428571 -0.3 -0.28571429 -0.27142857 -0.25714286 -0.24285714 -0.22857143 -0.21428571 -0.2 -0.18571429 -0.17142857 -0.15714286 -0.14285714 -0.12857143 -0.11428571 -0.1 -0.08571429 -0.07142857 -0.05714286 -0.04285714 -0.02857143 -0.01428571 0 0 0 0 0 0
  line L9 (21.3265, -3.1056) -> (20.2636, -2.5839)
  arc A19 (20.2172, -2.4516) -> (20.2636, -2.5839) centre (20.3077, -2.4941) ccw
  arc A20 (20.2172, -2.4516) -> (20.6618, -1.0832) centre (15, 0) ccw
  arc A21 (20.7771, -1.0035) -> (20.6618, -1.0832) centre (20.76, -1.102) ccw
  line L10 (20.7771, -1.0035) -> (21.9437, -1.2061)
  spline S10 degree 5 poles (21.9437, -1.2061) (21.9494, -1.2071) (21.9609, -1.2089) (21.9781, -1.211) (22.0011, -1.2127) (22.0301, -1.2132) (22.0593, -1.2127) (22.0885, -1.2115) (22.1178, -1.2099) (22.1471, -1.208) (22.1764, -1.2059) (22.2058, -1.2034) (22.2353, -1.2005) (22.2647, -1.197) (22.2943, -1.1929) (22.3238, -1.1884) (22.3534, -1.1833) (22.383, -1.178) (22.4126, -1.1723) (22.4422, -1.1663) (22.4719, -1.1599) (22.5015, -1.1533) (22.5312, -1.1463) (22.5609, -1.139) (22.5906, -1.1313) (22.6202, -1.1232) (22.6499, -1.1148) (22.6796, -1.1062) (22.7093, -1.0972) (22.7389, -1.0879) (22.7686, -1.0784) (22.7983, -1.0685) (22.8279, -1.0584) (22.8575, -1.048) (22.8872, -1.0372) (22.9168, -1.0262) (22.9464, -1.015) (22.9759, -1.0034) (23.0055, -0.9916) (23.035, -0.9795) (23.0645, -0.9671) (23.094, -0.9545) (23.1235, -0.9416) (23.1529, -0.9284) (23.1823, -0.915) (23.2117, -0.9013) (23.241, -0.8874) (23.2704, -0.8732) (23.2996, -0.8587) (23.3289, -0.844) (23.3581, -0.8291) (23.3873, -0.8139) (23.4164, -0.7985) (23.4455, -0.7828) (23.4746, -0.7669) (23.5036, -0.7508) (23.5325, -0.7344) (23.5615, -0.7177) (23.5903, -0.7009) (23.6192, -0.6838) (23.648, -0.6664) (23.6767, -0.6489) (23.7054, -0.6311) (23.734, -0.613) (23.7626, -0.5948) (23.7911, -0.5763) (23.8196, -0.5576) (23.848, -0.5387) (23.8764, -0.5195) (23.9047, -0.5001) (23.9329, -0.4805) (23.9555, -0.4647) (23.9723, -0.4527) (23.9836, -0.4446) (23.9892, -0.4406) knots 0 0 0 0 0 0 0.01428571 0.02857143 0.04285714 0.05714286 0.07142857 0.08571429 0.1 0.11428571 0.12857143 0.14285714 0.15714286 0.17142857 0.18571429 0.2 0.21428571 0.22857143 0.24285714 0.25714286 0.27142857 0.28571429 0.3 0.31428571 0.32857143 0.34285714 0.35714286 0.37142857 0.38571429 0.4 0.41428571 0.42857143 0.44285714 0.45714286 0.47142857 0.48571429 0.5 0.51428571 0.52857143 0.54285714 0.55714286 0.57142857 0.58571429 0.6 0.61428571 0.62857143 0.64285714 0.65714286 0.67142857 0.68571429 0.7 0.71428571 0.72857143 0.74285714 0.75714286 0.77142857 0.78571429 0.8 0.81428571 0.82857143 0.84285714 0.85714286 0.87142857 0.88571429 0.9 0.91428571 0.92857143 0.94285714 0.95714286 0.97142857 0.98571429 1 1 1 1 1 1
  arc A22 (23.9892, -0.4406) -> (23.9892, 0.4406) centre (15, 0) ccw
  spline S11 degree 5 poles (23.9892, 0.4406) (23.9836, 0.4446) (23.9723, 0.4527) (23.9555, 0.4647) (23.9329, 0.4805) (23.9047, 0.5001) (23.8764, 0.5195) (23.848, 0.5387) (23.8196, 0.5576) (23.7911, 0.5763) (23.7626, 0.5948) (23.734, 0.613) (23.7054, 0.6311) (23.6767, 0.6489) (23.648, 0.6664) (23.6192, 0.6838) (23.5903, 0.7009) (23.5615, 0.7177) (23.5325, 0.7344) (23.5036, 0.7508) (23.4746, 0.7669) (23.4455, 0.7828) (23.4164, 0.7985) (23.3873, 0.8139) (23.3581, 0.8291) (23.3289, 0.844) (23.2996, 0.8587) (23.2704, 0.8732) (23.241, 0.8874) (23.2117, 0.9013) (23.1823, 0.915) (23.1529, 0.9284) (23.1235, 0.9416) (23.094, 0.9545) (23.0645, 0.9671) (23.035, 0.9795) (23.0055, 0.9916) (22.9759, 1.0034) (22.9464, 1.015) (22.9168, 1.0262) (22.8872, 1.0372) (22.8575, 1.048) (22.8279, 1.0584) (22.7983, 1.0685) (22.7686, 1.0784) (22.7389, 1.0879) (22.7093, 1.0972) (22.6796, 1.1062) (22.6499, 1.1148) (22.6202, 1.1232) (22.5906, 1.1313) (22.5609, 1.139) (22.5312, 1.1463) (22.5015, 1.1533) (22.4719, 1.1599) (22.4422, 1.1663) (22.4126, 1.1723) (22.383, 1.178) (22.3534, 1.1833) (22.3238, 1.1884) (22.2943, 1.1929) (22.2647, 1.197) (22.2353, 1.2005) (22.2058, 1.2034) (22.1764, 1.2059) (22.1471, 1.208) (22.1178, 1.2099) (22.0885, 1.2115) (22.0593, 1.2127) (22.0301, 1.2132) (22.0011, 1.2127) (21.9781, 1.211) (21.9609, 1.2089) (21.9494, 1.2071) (21.9437, 1.2061) knots -1 -1 -1 -1 -1 -1 -0.98571429 -0.97142857 -0.95714286 -0.94285714 -0.92857143 -0.91428571 -0.9 -0.88571429 -0.87142857 -0.85714286 -0.84285714 -0.82857143 -0.81428571 -0.8 -0.78571429 -0.77142857 -0.75714286 -0.74285714 -0.72857143 -0.71428571 -0.7 -0.68571429 -0.67142857 -0.65714286 -0.64285714 -0.62857143 -0.61428571 -0.6 -0.58571429 -0.57142857 -0.55714286 -0.54285714 -0.52857143 -0.51428571 -0.5 -0.48571429 -0.47142857 -0.45714286 -0.44285714 -0.42857143 -0.41428571 -0.4 -0.38571429 -0.37142857 -0.35714286 -0.34285714 -0.32857143 -0.31428571 -0.3 -0.28571429 -0.27142857 -0.25714286 -0.24285714 -0.22857143 -0.21428571 -0.2 -0.18571429 -0.17142857 -0.15714286 -0.14285714 -0.12857143 -0.11428571 -0.1 -0.08571429 -0.07142857 -0.05714286 -0.04285714 -0.02857143 -0.01428571 0 0 0 0 0 0
  line L11 (21.9437, 1.2061) -> (20.7771, 1.0035)
  arc A23 (20.6618, 1.0832) -> (20.7771, 1.0035) centre (20.76, 1.102) ccw
  arc A24 (20.6618, 1.0832) -> (20.2172, 2.4516) centre (15, 0) ccw
  arc A25 (20.2636, 2.5839) -> (20.2172, 2.4516) centre (20.3077, 2.4941) ccw
  line L12 (20.2636, 2.5839) -> (21.3265, 3.1056)
  spline S12 degree 5 poles (21.3265, 3.1056) (21.3317, 3.1082) (21.342, 3.1135) (21.3572, 3.1219) (21.3768, 3.1341) (21.4006, 3.1507) (21.4239, 3.1683) (21.4468, 3.1864) (21.4695, 3.2049) (21.4922, 3.2236) (21.5147, 3.2426) (21.537, 3.2619) (21.5591, 3.2816) (21.5809, 3.3017) (21.6024, 3.3224) (21.6236, 3.3434) (21.6446, 3.3649) (21.6654, 3.3866) (21.686, 3.4086) (21.7064, 3.4309) (21.7267, 3.4534) (21.7468, 3.4763) (21.7667, 3.4993) (21.7863, 3.5227) (21.8058, 3.5464) (21.8251, 3.5704) (21.8442, 3.5946) (21.8631, 3.619) (21.8819, 3.6437) (21.9004, 3.6687) (21.9188, 3.6938) (21.937, 3.7192) (21.955, 3.7449) (21.9729, 3.7707) (21.9905, 3.7968) (22.008, 3.8231) (22.0253, 3.8496) (22.0425, 3.8764) (22.0594, 3.9033) (22.0762, 3.9305) (22.0928, 3.9578) (22.1092, 3.9854) (22.1255, 4.0131) (22.1415, 4.0411) (22.1574, 4.0692) (22.1732, 4.0976) (22.1887, 4.1261) (22.2041, 4.1548) (22.2193, 4.1837) (22.2343, 4.2127) (22.2492, 4.242) (22.2639, 4.2714) (22.2784, 4.301) (22.2927, 4.3308) (22.3068, 4.3608) (22.3208, 4.3909) (22.3346, 4.4212) (22.3482, 4.4516) (22.3617, 4.4823) (22.375, 4.5131) (22.3881, 4.544) (22.401, 4.5751) (22.4137, 4.6064) (22.4263, 4.6378) (22.4387, 4.6693) (22.4509, 4.7011) (22.4629, 4.7329) (22.4748, 4.765) (22.4865, 4.7971) (22.498, 4.8294) (22.5093, 4.8619) (22.5182, 4.888) (22.5249, 4.9076) (22.5292, 4.9207) (22.5314, 4.9273) knots 0 0 0 0 0 0 0.01428571 0.02857143 0.04285714 0.05714286 0.07142857 0.08571429 0.1 0.11428571 0.12857143 0.14285714 0.15714286 0.17142857 0.18571429 0.2 0.21428571 0.22857143 0.24285714 0.25714286 0.27142857 0.28571429 0.3 0.31428571 0.32857143 0.34285714 0.35714286 0.37142857 0.38571429 0.4 0.41428571 0.42857143 0.44285714 0.45714286 0.47142857 0.48571429 0.5 0.51428571 0.52857143 0.54285714 0.55714286 0.57142857 0.58571429 0.6 0.61428571 0.62857143 0.64285714 0.65714286 0.67142857 0.68571429 0.7 0.71428571 0.72857143 0.74285714 0.75714286 0.77142857 0.78571429 0.8 0.81428571 0.82857143 0.84285714 0.85714286 0.87142857 0.88571429 0.9 0.91428571 0.92857143 0.94285714 0.95714286 0.97142857 0.98571429 1 1 1 1 1 1
  arc A26 (22.5314, 4.9273) -> (22.0134, 5.6402) centre (15, 0) ccw
  spline S13 degree 5 poles (22.0134, 5.6402) (22.0065, 5.6401) (21.9927, 5.64) (21.972, 5.6398) (21.9444, 5.6394) (21.9101, 5.6386) (21.8758, 5.6377) (21.8416, 5.6365) (21.8075, 5.6351) (21.7734, 5.6335) (21.7395, 5.6317) (21.7056, 5.6297) (21.6719, 5.6274) (21.6382, 5.625) (21.6046, 5.6223) (21.5712, 5.6194) (21.5378, 5.6163) (21.5045, 5.613) (21.4713, 5.6094) (21.4383, 5.6056) (21.4053, 5.6017) (21.3724, 5.5975) (21.3397, 5.593) (21.307, 5.5884) (21.2745, 5.5835) (21.2421, 5.5784) (21.2098, 5.5731) (21.1776, 5.5676) (21.1456, 5.5619) (21.1136, 5.5559) (21.0818, 5.5497) (21.0501, 5.5433) (21.0186, 5.5366) (20.9872, 5.5297) (20.9559, 5.5226) (20.9248, 5.5153) (20.8938, 5.5077) (20.8629, 5.4999) (20.8322, 5.4919) (20.8016, 5.4836) (20.7712, 5.4751) (20.7409, 5.4664) (20.7108, 5.4574) (20.6809, 5.4482) (20.6511, 5.4387) (20.6215, 5.429) (20.592, 5.4191) (20.5627, 5.4089) (20.5336, 5.3984) (20.5047, 5.3878) (20.476, 5.3768) (20.4474, 5.3656) (20.4191, 5.3541) (20.391, 5.3423) (20.3631, 5.3303) (20.3354, 5.318) (20.3079, 5.3054) (20.2806, 5.2926) (20.2535, 5.2796) (20.2266, 5.2662) (20.2, 5.2525) (20.1737, 5.2385) (20.1478, 5.224) (20.1223, 5.2091) (20.097, 5.1938) (20.0721, 5.1783) (20.0473, 5.1625) (20.0226, 5.1466) (19.9983, 5.1304) (19.9744, 5.1137) (19.9513, 5.0962) (19.9336, 5.0813) (19.9209, 5.0695) (19.9127, 5.0613) (19.9086, 5.0572) knots -1 -1 -1 -1 -1 -1 -0.98571429 -0.97142857 -0.95714286 -0.94285714 -0.92857143 -0.91428571 -0.9 -0.88571429 -0.87142857 -0.85714286 -0.84285714 -0.82857143 -0.81428571 -0.8 -0.78571429 -0.77142857 -0.75714286 -0.74285714 -0.72857143 -0.71428571 -0.7 -0.68571429 -0.67142857 -0.65714286 -0.64285714 -0.62857143 -0.61428571 -0.6 -0.58571429 -0.57142857 -0.55714286 -0.54285714 -0.52857143 -0.51428571 -0.5 -0.48571429 -0.47142857 -0.45714286 -0.44285714 -0.42857143 -0.41428571 -0.4 -0.38571429 -0.37142857 -0.35714286 -0.34285714 -0.32857143 -0.31428571 -0.3 -0.28571429 -0.27142857 -0.25714286 -0.24285714 -0.22857143 -0.21428571 -0.2 -0.18571429 -0.17142857 -0.15714286 -0.14285714 -0.12857143 -0.11428571 -0.1 -0.08571429 -0.07142857 -0.05714286 -0.04285714 -0.02857143 -0.01428571 0 0 0 0 0 0
  line L13 (19.9086, 5.0572) -> (19.084, 4.2076)
  arc A27 (18.9438, 4.2043) -> (19.084, 4.2076) centre (19.0122, 4.2772) ccw
  arc A28 (18.9438, 4.2043) -> (17.7798, 5.05) centre (15, 0) ccw
  arc A29 (17.7396, 5.1843) -> (17.7798, 5.05) centre (17.828, 5.1376) ccw
  line L14 (17.7396, 5.1843) -> (18.2928, 6.2312)
  spline S14 degree 5 poles (18.2928, 6.2312) (18.2955, 6.2363) (18.3008, 6.2466) (18.3081, 6.2623) (18.3168, 6.2838) (18.3263, 6.3112) (18.3348, 6.339) (18.3426, 6.3672) (18.3502, 6.3955) (18.3575, 6.424) (18.3645, 6.4526) (18.3713, 6.4813) (18.3775, 6.5102) (18.3833, 6.5393) (18.3886, 6.5686) (18.3934, 6.5981) (18.3978, 6.6278) (18.4018, 6.6576) (18.4055, 6.6876) (18.409, 6.7176) (18.4121, 6.7477) (18.415, 6.778) (18.4175, 6.8084) (18.4196, 6.8389) (18.4215, 6.8695) (18.423, 6.9002) (18.4242, 6.931) (18.4252, 6.9619) (18.4258, 6.9929) (18.4262, 7.024) (18.4262, 7.0551) (18.426, 7.0864) (18.4256, 7.1177) (18.4248, 7.1491) (18.4238, 7.1806) (18.4224, 7.2122) (18.4208, 7.2438) (18.419, 7.2755) (18.4169, 7.3073) (18.4145, 7.3391) (18.4118, 7.371) (18.4089, 7.4029) (18.4058, 7.4349) (18.4023, 7.467) (18.3987, 7.4991) (18.3947, 7.5313) (18.3906, 7.5635) (18.3861, 7.5958) (18.3814, 7.6281) (18.3765, 7.6604) (18.3713, 7.6928) (18.3659, 7.7253) (18.3602, 7.7577) (18.3543, 7.7902) (18.3482, 7.8228) (18.3418, 7.8554) (18.3351, 7.888) (18.3282, 7.9206) (18.3211, 7.9533) (18.3138, 7.986) (18.3062, 8.0188) (18.2983, 8.0515) (18.2903, 8.0843) (18.282, 8.1171) (18.2735, 8.1499) (18.2647, 8.1828) (18.2557, 8.2156) (18.2465, 8.2485) (18.237, 8.2814) (18.2273, 8.3143) (18.2174, 8.3472) (18.2093, 8.3736) (18.2031, 8.3933) (18.199, 8.4065) (18.1969, 8.4131) knots 0 0 0 0 0 0 0.01428571 0.02857143 0.04285714 0.05714286 0.07142857 0.08571429 0.1 0.11428571 0.12857143 0.14285714 0.15714286 0.17142857 0.18571429 0.2 0.21428571 0.22857143 0.24285714 0.25714286 0.27142857 0.28571429 0.3 0.31428571 0.32857143 0.34285714 0.35714286 0.37142857 0.38571429 0.4 0.41428571 0.42857143 0.44285714 0.45714286 0.47142857 0.48571429 0.5 0.51428571 0.52857143 0.54285714 0.55714286 0.57142857 0.58571429 0.6 0.61428571 0.62857143 0.64285714 0.65714286 0.67142857 0.68571429 0.7 0.71428571 0.72857143 0.74285714 0.75714286 0.77142857 0.78571429 0.8 0.81428571 0.82857143 0.84285714 0.85714286 0.87142857 0.88571429 0.9 0.91428571 0.92857143 0.94285714 0.95714286 0.97142857 0.98571429 1 1 1 1 1 1
  arc A30 (18.1969, 8.4131) -> (17.3588, 8.6854) centre (15, 0) ccw
  spline S15 degree 5 poles (17.3588, 8.6854) (17.3532, 8.6813) (17.3421, 8.6731) (17.3255, 8.6607) (17.3034, 8.6442) (17.276, 8.6234) (17.2489, 8.6025) (17.2219, 8.5814) (17.1951, 8.5602) (17.1685, 8.5389) (17.1421, 8.5175) (17.1159, 8.496) (17.0899, 8.4743) (17.0641, 8.4525) (17.0386, 8.4306) (17.0132, 8.4086) (16.988, 8.3865) (16.963, 8.3642) (16.9383, 8.3419) (16.9137, 8.3194) (16.8894, 8.2968) (16.8653, 8.2741) (16.8414, 8.2512) (16.8177, 8.2283) (16.7943, 8.2052) (16.771, 8.1821) (16.748, 8.1588) (16.7252, 8.1354) (16.7027, 8.1119) (16.6804, 8.0883) (16.6583, 8.0646) (16.6364, 8.0408) (16.6148, 8.0168) (16.5934, 7.9928) (16.5723, 7.9687) (16.5514, 7.9444) (16.5308, 7.9201) (16.5104, 7.8956) (16.4903, 7.8711) (16.4704, 7.8464) (16.4508, 7.8217) (16.4314, 7.7968) (16.4124, 7.7719) (16.3936, 7.7468) (16.375, 7.7216) (16.3568, 7.6964) (16.3388, 7.671) (16.3211, 7.6456) (16.3037, 7.62) (16.2865, 7.5944) (16.2697, 7.5686) (16.2532, 7.5428) (16.2371, 7.5168) (16.2212, 7.4908) (16.2058, 7.4646) (16.1906, 7.4384) (16.1757, 7.4121) (16.1611, 7.3857) (16.1469, 7.3592) (16.133, 7.3326) (16.1195, 7.3059) (16.1065, 7.2791) (16.0941, 7.2521) (16.0822, 7.225) (16.0708, 7.1978) (16.0597, 7.1706) (16.0489, 7.1433) (16.0383, 7.1159) (16.0281, 7.0885) (16.0186, 7.061) (16.0102, 7.0332) (16.0046, 7.0108) (16.0013, 6.9937) (15.9995, 6.9823) (15.9986, 6.9766) knots -1 -1 -1 -1 -1 -1 -0.98571429 -0.97142857 -0.95714286 -0.94285714 -0.92857143 -0.91428571 -0.9 -0.88571429 -0.87142857 -0.85714286 -0.84285714 -0.82857143 -0.81428571 -0.8 -0.78571429 -0.77142857 -0.75714286 -0.74285714 -0.72857143 -0.71428571 -0.7 -0.68571429 -0.67142857 -0.65714286 -0.64285714 -0.62857143 -0.61428571 -0.6 -0.58571429 -0.57142857 -0.55714286 -0.54285714 -0.52857143 -0.51428571 -0.5 -0.48571429 -0.47142857 -0.45714286 -0.44285714 -0.42857143 -0.41428571 -0.4 -0.38571429 -0.37142857 -0.35714286 -0.34285714 -0.32857143 -0.31428571 -0.3 -0.28571429 -0.27142857 -0.25714286 -0.24285714 -0.22857143 -0.21428571 -0.2 -0.18571429 -0.17142857 -0.15714286 -0.14285714 -0.12857143 -0.11428571 -0.1 -0.08571429 -0.07142857 -0.05714286 -0.04285714 -0.02857143 -0.01428571 0 0 0 0 0 0
  line L15 (15.9986, 6.9766) -> (15.8309, 5.8045)
  arc A31 (15.7194, 5.7194) -> (15.8309, 5.8045) centre (15.7319, 5.8187) ccw
  arc A32 (15.7194, 5.7194) -> (14.2806, 5.7194) centre (15, 0) ccw
  arc A33 (14.1691, 5.8045) -> (14.2806, 5.7194) centre (14.2681, 5.8187) ccw
  line L16 (14.1691, 5.8045) -> (14.0014, 6.9766)
  spline S16 degree 5 poles (14.0014, 6.9766) (14.0005, 6.9823) (13.9987, 6.9937) (13.9954, 7.0108) (13.9898, 7.0332) (13.9814, 7.061) (13.9719, 7.0885) (13.9617, 7.1159) (13.9511, 7.1433) (13.9403, 7.1706) (13.9292, 7.1978) (13.9178, 7.225) (13.9059, 7.2521) (13.8935, 7.2791) (13.8805, 7.3059) (13.867, 7.3326) (13.8531, 7.3592) (13.8389, 7.3857) (13.8243, 7.4121) (13.8094, 7.4384) (13.7942, 7.4646) (13.7788, 7.4908) (13.7629, 7.5168) (13.7468, 7.5428) (13.7303, 7.5686) (13.7135, 7.5944) (13.6963, 7.62) (13.6789, 7.6456) (13.6612, 7.671) (13.6432, 7.6964) (13.625, 7.7216) (13.6064, 7.7468) (13.5876, 7.7719) (13.5686, 7.7968) (13.5492, 7.8217) (13.5296, 7.8464) (13.5097, 7.8711) (13.4896, 7.8956) (13.4692, 7.9201) (13.4486, 7.9444) (13.4277, 7.9687) (13.4066, 7.9928) (13.3852, 8.0168) (13.3636, 8.0408) (13.3417, 8.0646) (13.3196, 8.0883) (13.2973, 8.1119) (13.2748, 8.1354) (13.252, 8.1588) (13.229, 8.1821) (13.2057, 8.2052) (13.1823, 8.2283) (13.1586, 8.2512) (13.1347, 8.2741) (13.1106, 8.2968) (13.0863, 8.3194) (13.0617, 8.3419) (13.037, 8.3642) (13.012, 8.3865) (12.9868, 8.4086) (12.9614, 8.4306) (12.9359, 8.4525) (12.9101, 8.4743) (12.8841, 8.496) (12.8579, 8.5175) (12.8315, 8.5389) (12.8049, 8.5602) (12.7781, 8.5814) (12.7511, 8.6025) (12.724, 8.6234) (12.6966, 8.6442) (12.6745, 8.6607) (12.6579, 8.6731) (12.6468, 8.6813) (12.6412, 8.6854) knots 0 0 0 0 0 0 0.01428571 0.02857143 0.04285714 0.05714286 0.07142857 0.08571429 0.1 0.11428571 0.12857143 0.14285714 0.15714286 0.17142857 0.18571429 0.2 0.21428571 0.22857143 0.24285714 0.25714286 0.27142857 0.28571429 0.3 0.31428571 0.32857143 0.34285714 0.35714286 0.37142857 0.38571429 0.4 0.41428571 0.42857143 0.44285714 0.45714286 0.47142857 0.48571429 0.5 0.51428571 0.52857143 0.54285714 0.55714286 0.57142857 0.58571429 0.6 0.61428571 0.62857143 0.64285714 0.65714286 0.67142857 0.68571429 0.7 0.71428571 0.72857143 0.74285714 0.75714286 0.77142857 0.78571429 0.8 0.81428571 0.82857143 0.84285714 0.85714286 0.87142857 0.88571429 0.9 0.91428571 0.92857143 0.94285714 0.95714286 0.97142857 0.98571429 1 1 1 1 1 1
  arc A34 (12.6412, 8.6854) -> (11.8031, 8.4131) centre (15, 0) ccw